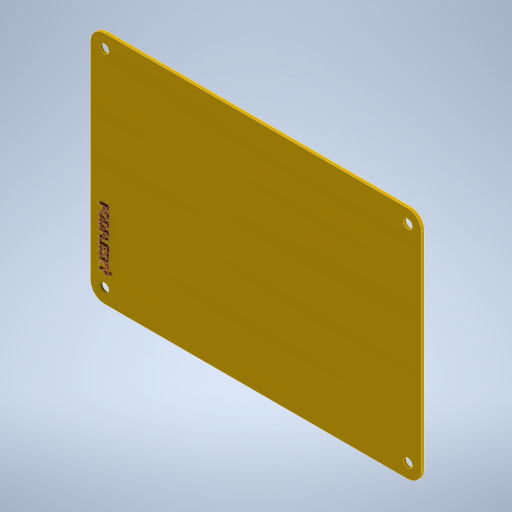
# Autodesk Inventor part: Deska spoje
Saved by Autodesk Inventor 2024 (Build 280153000, 153)
## iProperties
Created: 2025-09-30
Part Number: Deska spoje
Material: Všeobecné
Document SubType Name: Modeling
Designer: zak
Density: 1 g/cm^3
Appearance: Zlatá
Author: zak
Autodesk Inventor part; units mm, degrees
ref_plane "YZ Plane" through (0, 0, 0) normal (1, 0, 0) x (0, 1, 0)
ref_plane "XZ Plane" through (0, 0, 0) normal (0, 1, 0) x (-1, 0, 0)
ref_plane "XY Plane" through (0, 0, 0) normal (0, 0, 1) x (1, 0, 0)
sketch "Náčrt1" plane through (0, 0, 0) normal (0, 0, 1) x (1, 0, 0)
  line L0 (-84, 0) -> (84, 0) projected
  line L1 (0, -59.5) -> (0, 59.5) projected
  line L2 (-60, 42.5) -> (60, 42.5)
  line L3 (60, 42.5) -> (60, -42.5)
  line L4 (60, -42.5) -> (-60, -42.5)
  line L5 (-60, -42.5) -> (-60, 42.5)
  point P0 (0, 0)
  dimension "d0" = 120
  dimension "d1" = 85
  constraints: 8 end point, 2 parallel, 1 horizontal, 1 perpendicular, 2 other
  measures "d0" distance of L3.end L4.end
  measures "d1" distance of L2.end L3.end
extrude "Vysunutí1" add sketch "Náčrt1" along normal mid plane 1
fillet "Zaoblení1" radius 5 4 edges at (60, 42.5, 0) (-60, 42.5, 0) (60, -42.5, 0) (-60, -42.5, 0)
sketch "Náčrt2" plane through (0, 0, 0.5) normal (0, 0, 1) x (1, 0, 0)
  arc A0 (-55, 42.5) -> (-60, 37.5) centre (-55, 37.5) ccw projected
  arc A1 (60, 37.5) -> (55, 42.5) centre (55, 37.5) ccw projected
  arc A2 (55, -42.5) -> (60, -37.5) centre (55, -37.5) ccw projected
  arc A3 (-60, -37.5) -> (-55, -42.5) centre (-55, -37.5) ccw projected
  point P0 (0, 0)
  constraints: 4 coincident
hole "Díra1" at (-55, 37.5, 0.5) at (55, 37.5, 0.5) at (55, -37.5, 0.5) at (-55, -37.5, 0.5) direction (0, 0, -1) diameter 3.4 end through all clearance for "Šroub se zápustnou hlavou ISO 2009/7046" size "M3" standard "ISO"
sketch "Náčrt3" plane through (0, 0, 0.5) normal (0, 0, 1) x (1, 0, 0)
  line L0 (-52, -10.5) -> (-52, -32.5) construction
  line L1 (-52, -32.5) -> (-57, -32.5) construction
  line L2 (-57, -32.5) -> (-57, -10.5) construction
  line L3 (-57, -10.5) -> (-52, -10.5) construction
  line L4 (-60, 37.5) -> (-60, -37.5) projected
  circle A0 centre (-55, -37.5) radius 1.7 projected
  spline S0 degree 2 poles (-54.0649, -12.7354) (-54.2625, -12.7354) (-54.6182, -12.5946) (-54.7417, -12.4686) knots 0 0 0 1 2 2 2
  spline S1 degree 2 poles (-54.7417, -12.4686) (-54.8973, -12.3105) (-55.0579, -11.8832) (-55.0579, -11.5572) knots 0 0 0 1 2 2 2
  line L5 (-55.0579, -11.5572) -> (-55.0579, -11.2138)
  line L6 (-55.0579, -11.2138) -> (-56.1941, -11.2138)
  line L7 (-56.1941, -11.2138) -> (-56.1941, -10.8088)
  line L8 (-56.1941, -10.8088) -> (-53.1461, -10.8088)
  line L9 (-53.1461, -10.8088) -> (-53.1461, -11.5745)
  spline S2 degree 2 poles (-53.1461, -11.5745) (-53.1461, -11.8462) (-53.235, -12.2265) (-53.3363, -12.3723) knots 0 0 0 1 2 2 2
  spline S3 degree 2 poles (-53.3363, -12.3723) (-53.4524, -12.5427) (-53.8105, -12.7354) (-54.0649, -12.7354) knots 0 0 0 1 2 2 2
  spline S4 degree 2 poles (-54.0773, -12.313) (-53.9192, -12.313) (-53.687, -12.2043) (-53.6129, -12.0932) knots 0 0 0 1 2 2 2
  spline S5 degree 2 poles (-53.6129, -12.0932) (-53.5487, -11.9968) (-53.4968, -11.7399) (-53.4968, -11.5498) knots 0 0 0 1 2 2 2
  line L10 (-53.4968, -11.5498) -> (-53.4968, -11.2138)
  line L11 (-53.4968, -11.2138) -> (-54.7121, -11.2138)
  line L12 (-54.7121, -11.2138) -> (-54.7121, -11.4905)
  spline S6 degree 2 poles (-54.7121, -11.4905) (-54.7121, -11.7375) (-54.633, -12.0413) (-54.5293, -12.1401) knots 0 0 0 1 2 2 2
  spline S7 degree 2 poles (-54.5293, -12.1401) (-54.4379, -12.2315) (-54.223, -12.313) (-54.0773, -12.313) knots 0 0 0 1 2 2 2
  spline S8 degree 2 poles (-53.4944, -15.277) (-53.6969, -15.4499) (-54.2897, -15.6426) (-54.6701, -15.6426) knots 0 0 0 1 2 2 2
  spline S9 degree 2 poles (-54.6701, -15.6426) (-55.0406, -15.6426) (-55.6408, -15.4549) (-55.8433, -15.277) knots 0 0 0 1 2 2 2
  spline S10 degree 2 poles (-55.8433, -15.277) (-56.0558, -15.0893) (-56.2583, -14.5928) (-56.2583, -14.2939) knots 0 0 0 1 2 2 2
  spline S11 degree 2 poles (-56.2583, -14.2939) (-56.2583, -13.9852) (-56.0484, -13.4912) (-55.8433, -13.3109) knots 0 0 0 1 2 2 2
  spline S12 degree 2 poles (-55.8433, -13.3109) (-55.6408, -13.1355) (-55.0455, -12.9478) (-54.6701, -12.9478) knots 0 0 0 1 2 2 2
  spline S13 degree 2 poles (-54.6701, -12.9478) (-54.2872, -12.9478) (-53.7043, -13.138) (-53.4944, -13.3133) knots 0 0 0 1 2 2 2
  spline S14 degree 2 poles (-53.4944, -13.3133) (-53.2918, -13.4912) (-53.0819, -13.9877) (-53.0819, -14.2939) knots 0 0 0 1 2 2 2
  spline S15 degree 2 poles (-53.0819, -14.2939) (-53.0819, -14.6052) (-53.2992, -15.1041) (-53.4944, -15.277) knots 0 0 0 1 2 2 2
  spline S16 degree 2 poles (-54.6701, -15.2202) (-54.3687, -15.2202) (-53.9019, -15.0893) (-53.7488, -14.9707) knots 0 0 0 1 2 2 2
  spline S17 degree 2 poles (-53.7488, -14.9707) (-53.5907, -14.8497) (-53.4326, -14.5088) (-53.4326, -14.2964) knots 0 0 0 1 2 2 2
  spline S18 degree 2 poles (-53.4326, -14.2964) (-53.4326, -14.0766) (-53.5858, -13.7456) (-53.7488, -13.6196) knots 0 0 0 1 2 2 2
  spline S19 degree 2 poles (-53.7488, -13.6196) (-53.9044, -13.4986) (-54.3737, -13.3702) (-54.6701, -13.3702) knots 0 0 0 1 2 2 2
  spline S20 degree 2 poles (-54.6701, -13.3702) (-55.2703, -13.3702) (-55.9076, -13.874) (-55.9076, -14.2964) knots 0 0 0 1 2 2 2
  spline S21 degree 2 poles (-55.9076, -14.2964) (-55.9076, -14.7188) (-55.2703, -15.2202) (-54.6701, -15.2202) knots 0 0 0 1 2 2 2
  spline S22 degree 2 poles (-54.6726, -18.4905) (-55.09, -18.4905) (-55.7618, -18.1521) (-55.9496, -17.8681) knots 0 0 0 1 2 2 2
  spline S23 degree 2 poles (-55.9496, -17.8681) (-56.0953, -17.6359) (-56.1941, -17.1592) (-56.1941, -16.7887) knots 0 0 0 1 2 2 2
  line L13 (-56.1941, -16.7887) -> (-56.1941, -16.0872)
  line L14 (-56.1941, -16.0872) -> (-53.1461, -16.0872)
  line L15 (-53.1461, -16.0872) -> (-53.1461, -16.7813)
  spline S24 degree 2 poles (-53.1461, -16.7813) (-53.1461, -17.211) (-53.2745, -17.7001) (-53.3881, -17.873) knots 0 0 0 1 2 2 2
  spline S25 degree 2 poles (-53.3881, -17.873) (-53.5833, -18.1669) (-54.228, -18.4905) (-54.6726, -18.4905) knots 0 0 0 1 2 2 2
  spline S26 degree 2 poles (-54.6676, -18.0681) (-54.3169, -18.0681) (-53.8204, -17.8359) (-53.6796, -17.6062) knots 0 0 0 1 2 2 2
  spline S27 degree 2 poles (-53.6796, -17.6062) (-53.5833, -17.4432) (-53.4968, -17.0752) (-53.4968, -16.801) knots 0 0 0 1 2 2 2
  line L16 (-53.4968, -16.801) -> (-53.4968, -16.4923)
  line L17 (-53.4968, -16.4923) -> (-55.8433, -16.4923)
  line L18 (-55.8433, -16.4923) -> (-55.8433, -16.801)
  spline S28 degree 2 poles (-55.8433, -16.801) (-55.8433, -17.0702) (-55.7569, -17.4778) (-55.6408, -17.6433) knots 0 0 0 1 2 2 2
  spline S29 degree 2 poles (-55.6408, -17.6433) (-55.4975, -17.8557) (-55.0233, -18.0681) (-54.6676, -18.0681) knots 0 0 0 1 2 2 2
  spline S30 degree 2 poles (-54.0649, -20.8568) (-54.2625, -20.8568) (-54.6182, -20.716) (-54.7417, -20.59) knots 0 0 0 1 2 2 2
  spline S31 degree 2 poles (-54.7417, -20.59) (-54.8973, -20.4319) (-55.0579, -20.0046) (-55.0579, -19.6786) knots 0 0 0 1 2 2 2
  line L19 (-55.0579, -19.6786) -> (-55.0579, -19.3352)
  line L20 (-55.0579, -19.3352) -> (-56.1941, -19.3352)
  line L21 (-56.1941, -19.3352) -> (-56.1941, -18.9302)
  line L22 (-56.1941, -18.9302) -> (-53.1461, -18.9302)
  line L23 (-53.1461, -18.9302) -> (-53.1461, -19.6959)
  spline S32 degree 2 poles (-53.1461, -19.6959) (-53.1461, -19.9676) (-53.235, -20.348) (-53.3363, -20.4937) knots 0 0 0 1 2 2 2
  spline S33 degree 2 poles (-53.3363, -20.4937) (-53.4524, -20.6641) (-53.8105, -20.8568) (-54.0649, -20.8568) knots 0 0 0 1 2 2 2
  spline S34 degree 2 poles (-54.0773, -20.4344) (-53.9192, -20.4344) (-53.687, -20.3257) (-53.6129, -20.2146) knots 0 0 0 1 2 2 2
  spline S35 degree 2 poles (-53.6129, -20.2146) (-53.5487, -20.1182) (-53.4968, -19.8614) (-53.4968, -19.6712) knots 0 0 0 1 2 2 2
  line L24 (-53.4968, -19.6712) -> (-53.4968, -19.3352)
  line L25 (-53.4968, -19.3352) -> (-54.7121, -19.3352)
  line L26 (-54.7121, -19.3352) -> (-54.7121, -19.6119)
  spline S36 degree 2 poles (-54.7121, -19.6119) (-54.7121, -19.8589) (-54.633, -20.1627) (-54.5293, -20.2615) knots 0 0 0 1 2 2 2
  spline S37 degree 2 poles (-54.5293, -20.2615) (-54.4379, -20.3529) (-54.223, -20.4344) (-54.0773, -20.4344) knots 0 0 0 1 2 2 2
  line L27 (-56.1941, -23.0082) -> (-56.1941, -21.2421)
  line L28 (-56.1941, -21.2421) -> (-53.1461, -21.2421)
  line L29 (-53.1461, -21.2421) -> (-53.1461, -21.6472)
  line L30 (-53.1461, -21.6472) -> (-55.8335, -21.6472)
  line L31 (-55.8335, -21.6472) -> (-55.8335, -23.0082)
  line L32 (-55.8335, -23.0082) -> (-56.1941, -23.0082)
  line L33 (-56.1941, -23.3268) -> (-53.1461, -23.3268)
  line L34 (-53.1461, -23.3268) -> (-53.1461, -25.2336)
  line L35 (-53.1461, -25.2336) -> (-53.5067, -25.2336)
  line L36 (-53.5067, -25.2336) -> (-53.5067, -23.7319)
  line L37 (-53.5067, -23.7319) -> (-54.3416, -23.7319)
  line L38 (-54.3416, -23.7319) -> (-54.3416, -25.1324)
  line L39 (-54.3416, -25.1324) -> (-54.7022, -25.1324)
  line L40 (-54.7022, -25.1324) -> (-54.7022, -23.7319)
  line L41 (-54.7022, -23.7319) -> (-55.8335, -23.7319)
  line L42 (-55.8335, -23.7319) -> (-55.8335, -25.2336)
  line L43 (-55.8335, -25.2336) -> (-56.1941, -25.2336)
  line L44 (-56.1941, -25.2336) -> (-56.1941, -23.3268)
  spline S38 degree 2 poles (-56.2484, -26.5279) (-56.2484, -26.197) (-56.1101, -25.7326) (-56.0113, -25.5276) knots 0 0 0 1 2 2 2
  line L45 (-56.0113, -25.5276) -> (-55.5025, -25.5276)
  line L46 (-55.5025, -25.5276) -> (-55.5025, -25.5572)
  spline S39 degree 2 poles (-55.5025, -25.5572) (-55.6902, -25.7573) (-55.8977, -26.2636) (-55.8977, -26.4983) knots 0 0 0 1 2 2 2
  spline S40 degree 2 poles (-55.8977, -26.4983) (-55.8977, -26.8342) (-55.6186, -27.1775) (-55.3889, -27.1775) knots 0 0 0 1 2 2 2
  spline S41 degree 2 poles (-55.3889, -27.1775) (-55.2061, -27.1775) (-54.9788, -26.9972) (-54.922, -26.8021) knots 0 0 0 1 2 2 2
  spline S42 degree 2 poles (-54.922, -26.8021) (-54.8825, -26.6613) (-54.8282, -26.4267) (-54.7837, -26.2513) knots 0 0 0 1 2 2 2
  spline S43 degree 2 poles (-54.7837, -26.2513) (-54.7417, -26.0932) (-54.6157, -25.8437) (-54.5145, -25.7474) knots 0 0 0 1 2 2 2
  spline S44 degree 2 poles (-54.5145, -25.7474) (-54.4132, -25.6535) (-54.1415, -25.5498) (-53.9637, -25.5498) knots 0 0 0 1 2 2 2
  spline S45 degree 2 poles (-53.9637, -25.5498) (-53.5932, -25.5498) (-53.0917, -26.1278) (-53.0917, -26.5749) knots 0 0 0 1 2 2 2
  spline S46 degree 2 poles (-53.0917, -26.5749) (-53.0917, -26.8317) (-53.193, -27.2862) (-53.2893, -27.4814) knots 0 0 0 1 2 2 2
  line L47 (-53.2893, -27.4814) -> (-53.7735, -27.4814)
  line L48 (-53.7735, -27.4814) -> (-53.7735, -27.4517)
  spline S47 degree 2 poles (-53.7735, -27.4517) (-53.6401, -27.306) (-53.4425, -26.8515) (-53.4425, -26.602) knots 0 0 0 1 2 2 2
  spline S48 degree 2 poles (-53.4425, -26.602) (-53.4425, -26.3205) (-53.7068, -25.9722) (-53.9217, -25.9722) knots 0 0 0 1 2 2 2
  spline S49 degree 2 poles (-53.9217, -25.9722) (-54.1143, -25.9722) (-54.344, -26.1772) (-54.3959, -26.3699) knots 0 0 0 1 2 2 2
  spline S50 degree 2 poles (-54.3959, -26.3699) (-54.4305, -26.4983) (-54.5194, -26.8713) (-54.5565, -26.9948) knots 0 0 0 1 2 2 2
  spline S51 degree 2 poles (-54.5565, -26.9948) (-54.6528, -27.3085) (-55.0406, -27.5999) (-55.3246, -27.5999) knots 0 0 0 1 2 2 2
  spline S52 degree 2 poles (-55.3246, -27.5999) (-55.505, -27.5999) (-55.8508, -27.4542) (-55.9718, -27.3233) knots 0 0 0 1 2 2 2
  spline S53 degree 2 poles (-55.9718, -27.3233) (-56.1052, -27.1775) (-56.2484, -26.807) (-56.2484, -26.5279) knots 0 0 0 1 2 2 2
  line L49 (-56.1941, -30.2354) -> (-56.1941, -29.7093)
  line L50 (-56.1941, -29.7093) -> (-54.7763, -28.5953)
  line L51 (-54.7763, -28.5953) -> (-54.9764, -28.4175)
  line L52 (-54.9764, -28.4175) -> (-56.1941, -28.4175)
  line L53 (-56.1941, -28.4175) -> (-56.1941, -28.0124)
  line L54 (-56.1941, -28.0124) -> (-53.1461, -28.0124)
  line L55 (-53.1461, -28.0124) -> (-53.1461, -28.4175)
  line L56 (-53.1461, -28.4175) -> (-54.5466, -28.4175)
  line L57 (-54.5466, -28.4175) -> (-53.1461, -29.6673)
  line L58 (-53.1461, -29.6673) -> (-53.1461, -30.1613)
  line L59 (-53.1461, -30.1613) -> (-54.5071, -28.8992)
  line L60 (-54.5071, -28.8992) -> (-56.1941, -30.2354)
  line L61 (-53.1461, -32.6116) -> (-54.8455, -31.5816)
  line L62 (-54.8455, -31.5816) -> (-56.1941, -31.5816)
  line L63 (-56.1941, -31.5816) -> (-56.1941, -31.1765)
  line L64 (-56.1941, -31.1765) -> (-54.8874, -31.1765)
  line L65 (-54.8874, -31.1765) -> (-53.1461, -30.1465)
  line L66 (-53.1461, -30.1465) -> (-53.1461, -30.5961)
  line L67 (-53.1461, -30.5961) -> (-54.4873, -31.3815)
  line L68 (-54.4873, -31.3815) -> (-53.1461, -32.1818)
  line L69 (-53.1461, -32.1818) -> (-53.1461, -32.6116)
  line L70 (-52, -31.9916) -> (-52.7657, -31.4334)
  line L71 (-52.7657, -31.4334) -> (-52.7657, -31.1271)
  line L72 (-52.7657, -31.1271) -> (-52, -31.4927)
  line L73 (-52, -31.4927) -> (-52, -31.9916)
  point P0 (0, 0)
  point P1 (-54.5, -32.5)
  dimension "d14" = 3
  dimension "d15" = 5
  dimension "d16" = 5
  dimension "d17" = 22
  constraints: 1 midpoint, 2 other
  measures "d14" distance between parallel lines of L4 L2
  measures "d15" vertical distance of A0.centre point (-54.5, -32.5)
  measures "d16" distance between parallel lines of L2 L0
  measures "d17" distance between parallel lines of L1 L3
emboss "Reliéf1" sketch "Náčrt3" operation add depth 1 direction (0, 0, -1) contours S0 S1 L5 L6 L7 L8 L9 S2 S3 | S8 S9 S10 S11 S12 S13 S14 S15 | S22 S23 L13 L14 L15 S24 S25 | S30 S31 L19 L20 L21 L22 L23 S32 S33 | L27 L28 L29 L30 L31 L32 | L33 L34 L35 L36 L37 L38 L39 L40 L41 L42 L43 L44 | S38 L45 L46 S39 S40 S41 S42 S43 S44 S45 S46 L47 L48 S47 S48 S49 S50 S51 S52 S53 | L49 L50 L51 L52 L53 L54 L55 L56 L57 L58 L65 L59 L60 | L65 L58 L59 | L59 L66 L67 L68 L69 L61 L62 L63 L64 L65 | L70 L71 L72 L73
